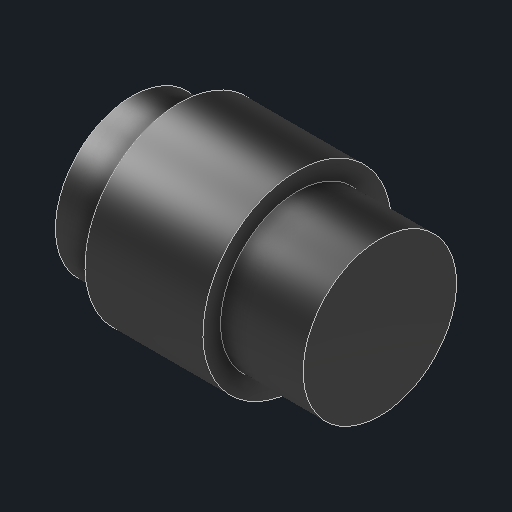
# Autodesk Inventor part: polar_scope
Saved by Autodesk Inventor 2027.1 (Build 311270010, 270A)
## iProperties
Created: 2026-11-04
Part Number: polar_scope
Material: Generic
Description: Polar scope eyepiece end
Document SubType Name: Modeling
Designer: Claude (from photos)
Density: 1 g/cm^3
Appearance: Glossy - Black
Author: alexg
Autodesk Inventor part; units mm, degrees
ref_plane "XZ Plane" through (0, 0, 0) normal (0, 1, 0) x (-1, 0, 0)
ref_plane "XY Plane" through (0, 0, 0) normal (0, 0, 1) x (1, 0, 0)
sketch "Polar scope body sketch" plane through (0, 0, 0) normal (0, 0, 1) x (1, 0, 0)
  line L0 (-14, 0) -> (-42, 0)
  line L1 (-42, 0) -> (-42, 13)
  line L2 (-42, 13) -> (-34, 13)
  line L3 (-34, 13) -> (-34, 16)
  line L4 (-34, 16) -> (-14, 16)
  line L5 (-14, 16) -> (-14, 0)
  constraints: 12 end point
revolve "Polar scope body" add sketch "Polar scope body sketch" angle 360 about axis through (-14, 0, 0) along (-1, 0, 0)
ref_plane "Work Plane1" through (-14, 0, 0) normal (1, 0, 0) x (0, 1, 0)
sketch "Spigot sketch" plane through (-14, 0, 0) normal (1, 0, 0) x (0, 1, 0)
  circle A0 centre (0, 0) radius 13
  constraints: 1 centre point
extrude "Spigot" add sketch "Spigot sketch" along normal blind 14
body "Solid1"
